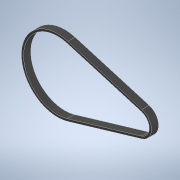
# Autodesk Inventor part: TiminigBelt_F
Saved by Autodesk Inventor 2021 (Build 250183000, 183)
## iProperties
Created: 2025-11-24
Part Number: TiminigBelt_F
Material: Rubber, Silicone
Document SubType Name: Modeling
Designer: Admin
Density: 1.25 g/cm^3
Appearance: Rubber - Black
Author: Admin
Autodesk Inventor part; units mm, degrees
ref_plane "YZ Plane" through (0, 0, 0) normal (1, 0, 0) x (0, 1, 0)
ref_plane "XZ Plane" through (0, 0, 0) normal (0, 1, 0) x (-1, 0, 0)
ref_plane "XY Plane" through (0, 0, 0) normal (0, 0, 1) x (1, 0, 0)
sketch "Sketch1" plane through (0, 0, 0) normal (0, 0, 1) x (1, 0, 0)
  arc A0 (13.4475, 45.3742) -> (13.4475, -45.3742) centre (0, 0) ccw
  arc A1 (116.4044, -14.8611) -> (116.4044, 14.8611) centre (112, 0) ccw
  line L0 (13.4475, 45.3742) -> (116.4044, 14.8611)
  line L1 (13.4475, -45.3742) -> (116.4044, -14.8611)
  line L2 (-86.49, 0) -> (166.665, 0) projected
  line L3 (117.2568, 17.7374) -> (14.2999, 48.2506)
  arc A2 (14.2999, 48.2506) -> (14.2999, -48.2506) centre (0, 0) ccw
  line L4 (14.2999, -48.2506) -> (117.2568, -17.7374)
  arc A3 (117.2568, -17.7374) -> (117.2568, 17.7374) centre (112, 0) ccw
  dimension "d0" = 112
  dimension "d1" = 94.65
  dimension "d2" = 31
  dimension "d3" = 0
  dimension "d20" = 3
  constraints: 8 end point, 8 point on circle, 4 centre point, 4 tangent, 1 coincident, 3 other
  measures "d0" distance of A1.centre point (0, 0)
  measures "d1" diameter of A0
  measures "d2" diameter of A1
  measures "d3" vertical distance of point (0, 0) A1.centre
  measures "d20" distance between parallel lines of L0 L3
extrude "Extrusion2" add sketch "Sketch1" along normal mid plane 10 contours A0 L2 A2 L3 A3 A1 L0 | A0 L1 A1 L2 A3 L4 A2
body "Solid2"
